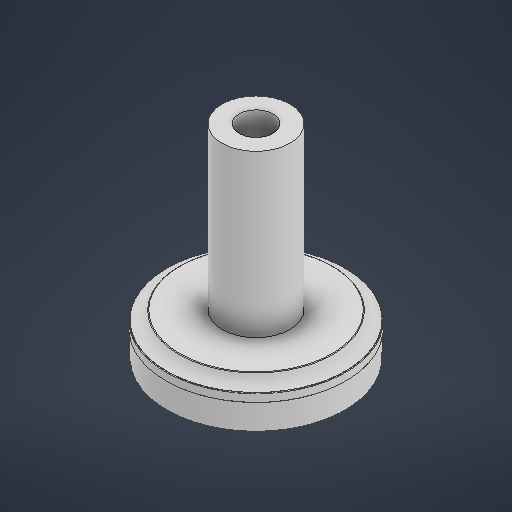
# Autodesk Inventor part: 22.10.2025-03
Saved by Autodesk Inventor 2026.1 (Build 301233020, 233B)
## iProperties
Created: 2025-10-22
Part Number: 22.10.2025-03
Material: Ogólny
Document SubType Name: Modeling
Designer: Nitro
Density: 1 g/cm^3
Appearance: Domyślna
Author: Nitro
Autodesk Inventor part; units mm, degrees
ref_plane "YZ Plane" through (0, 0, 0) normal (1, 0, 0) x (0, 1, 0)
ref_plane "XZ Plane" through (0, 0, 0) normal (0, 1, 0) x (-1, 0, 0)
ref_plane "XY Plane" through (0, 0, 0) normal (0, 0, 1) x (1, 0, 0)
sketch "Szkic1" plane through (0, 0, 0) normal (0, 0, 1) x (1, 0, 0)
  line L0 (0, -35) -> (-20, -35)
  line L1 (-20, -35) -> (-20, -15)
  line L2 (-20, -15) -> (-26, -15)
  line L3 (-26, -15) -> (-26, -5)
  line L4 (-26, -5) -> (-50.5, -5)
  line L5 (-50.5, -5) -> (-50.5, -20)
  line L6 (-50.5, -20) -> (-52.5, -20)
  line L7 (-52.5, -20) -> (-52.5, 0)
  line L8 (-52.5, 0) -> (0, 0)
  line L9 (0, 0) -> (0, -35)
  line L10 (0, 0) -> (-10, 0)
  line L11 (-10, 0) -> (-10, 100)
  line L12 (-10, 0) -> (-20, 0)
  line L13 (-20, 0) -> (-20, 100)
  line L14 (-20, 100) -> (-10, 100)
  line L15 (-20, 0) -> (-20, 40)
  line L16 (-20, 0) -> (-45, 0)
  line L17 (-20, 0) -> (-20, 5)
  line L18 (-20, 5) -> (-45, 5)
  line L19 (-45, 5) -> (-45, 0)
  arc A0 (-52.5, 0) -> (-45, 5) centre (-52.5, 8.125) ccw
  line L20 (-52.5, -5) -> (-53, -5)
  line L21 (-53, -5) -> (-53, 0)
  line L22 (-53, 0) -> (-52.5, 0)
  dimension "d0" = 35
  dimension "d1" = 26
  dimension "d2" = 20
  dimension "d3" = 50.5
  dimension "d4" = 2
  dimension "d5" = 20
  dimension "d6" = 20
  dimension "d7" = 10
  dimension "d8" = 10
  dimension "d9" = 100
  dimension "d10" = 100
  dimension "d11" = 10
  dimension "d12" = 40
  dimension "d13" = 25
  dimension "d14" = 5
  dimension "d15" = 0.5
  dimension "d16" = 5
  constraints: 46 end point, 16 perpendicular, 6 point on line, 2 point on circle, 1 centre point, 1 coincident, 1 tangent, 1 vertical
  measures "d0" distance of L8.end L0.start
  measures "d1" horizontal distance of L0.start L2.end
  measures "d2" distance of L0.start L0.end
  measures "d3" horizontal distance of L0.start L5.end
  measures "d4" distance of L5.end L6.end
  measures "d5" distance of L6.end L7.end
  measures "d6" distance of L1.end L0.end
  measures "d7" distance of L2.end L3.end
  measures "d8" distance of L8.end L10.end
  measures "d9" distance of L10.end L11.end
  measures "d10" distance of L12.end L13.end
  measures "d11" distance of L11.end L13.end
  measures "d12" distance of L12.end L15.end
  measures "d13" distance of L12.end L16.end
  measures "d14" distance of L12.end L17.end
  measures "d15" distance of L20.start L20.end
  measures "d16" distance of L20.end L21.end
revolve "Obrót1" add sketch "Szkic1" angle 360 about axis through (0, 0, 0) along (0, -1, 0)
fillet "Zaokrąglenie1" radius 0.3 1 edges at (53, -5, 0)
fillet "Zaokrąglenie2" radius 0.3 1 edges at (53, 0, 0)
chamfer "Faza1" distance 0.3 angle 45 1 edges at (45, 5, 0)
chamfer "Faza2" distance 2 angle 45 1 edges at (20, -35, 0)
fillet "Zaokrąglenie3" radius 0.2 2 edges at (52.5, -20, 0) (50.5, -20, 0)
chamfer "Faza3" distance 1 angle 45 1 edges at (50.5, -5, 0)
chamfer "Faza4" distance 1 angle 45 1 edges at (26, -5, 0)
